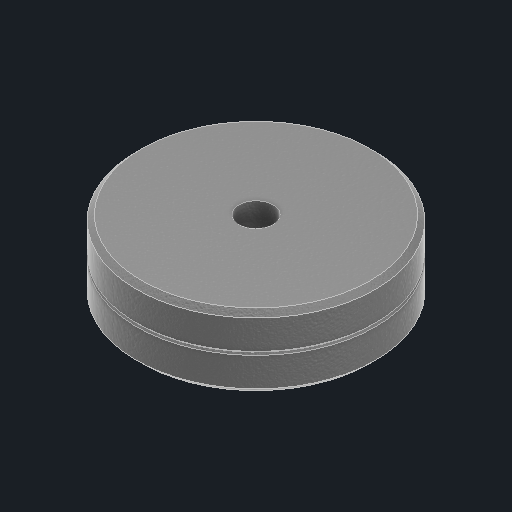
# Autodesk Inventor part: counterweight_5kg
Saved by Autodesk Inventor 2027.1 (Build 311270010, 270A)
## iProperties
Created: 2026-11-04
Part Number: counterweight_5kg
Material: Generic
Description: Counterweight ~5 kg (11 lb), 140 x 42 mm, 20 mm bore
Document SubType Name: Modeling
Designer: Claude (from photos)
Density: 1 g/cm^3
Appearance: Coarse Textured - Dark Gray
Author: alexg
Autodesk Inventor part; units mm, degrees
ref_plane "XZ Plane" through (0, 0, 0) normal (0, 1, 0) x (-1, 0, 0)
ref_plane "XY Plane" through (0, 0, 0) normal (0, 0, 1) x (1, 0, 0)
sketch "Counterweight 140x42 sketch" plane through (0, 0, 0) normal (0, 0, 1) x (1, 0, 0)
  line L0 (10, -21) -> (67, -21)
  line L1 (67, -21) -> (70, -18)
  line L2 (70, -18) -> (70, -1)
  line L3 (70, -1) -> (69, 0)
  line L4 (69, 0) -> (70, 1)
  line L5 (70, 1) -> (70, 18)
  line L6 (70, 18) -> (67, 21)
  line L7 (67, 21) -> (10, 21)
  line L8 (10, 21) -> (10, -21)
  line L9 (0, -29.4) -> (0, 29.4) projected
  constraints: 18 end point
revolve "Counterweight 140x42" add sketch "Counterweight 140x42 sketch" angle 360 about axis through (0, -10, 0) along (0, 1, 0)
ref_plane "Work Plane1" through (-75, 0, 0) normal (1, 0, 0) x (0, 1, 0)
sketch "Lock screw thread sketch" plane through (-75, 0, 0) normal (1, 0, 0) x (0, 1, 0)
  circle A0 centre (0, 0) radius 4
  constraints: 1 centre point
extrude "Lock screw thread" cut sketch "Lock screw thread sketch" along normal blind 70
body "Solid1"
